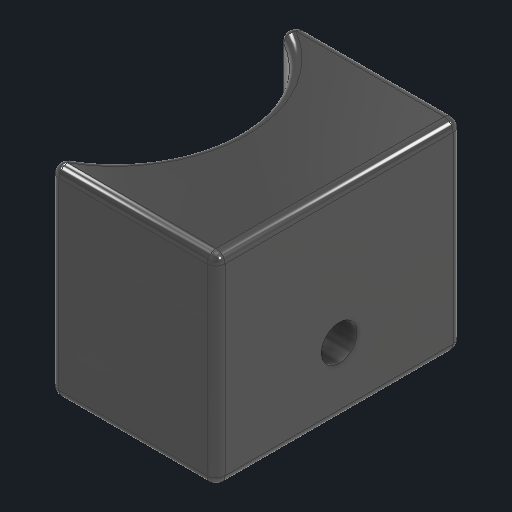
# Autodesk Inventor part: CylinderEndEffector
Saved by Autodesk Inventor 2027.1 (Build 311270010, 270A)
## iProperties
Created: 2026-10-14
Part Number: CylinderEndEffector
Material: PC/ABS Plastic
Document SubType Name: Modeling
Designer: SDS Scholar
Density: 1.1 g/cm^3
Appearance: Smooth - White
Mass: 74.7536 g
Surface Area: 116.939 cm^2
Volume: 67.9578 cm^3
Author: SDS Scholar
Autodesk Inventor part; units mm, degrees
ref_plane "YZ Plane" through (0, 0, 0) normal (1, 0, 0) x (0, 1, 0)
ref_plane "XZ Plane" through (0, 0, 0) normal (0, 1, 0) x (-1, 0, 0)
ref_plane "XY Plane" through (0, 0, 0) normal (0, 0, 1) x (1, 0, 0)
sketch "Sketch1" plane through (0, 0, 0) normal (0, 1, 0) x (-1, 0, 0)
  circle A0 centre (0, 0) radius 27.5
  line L0 (0, 27.5) -> (-50, 27.5)
  line L1 (27.5, 0) -> (-27.5, 0) construction
  line L2 (0, -27.5) -> (-50, -27.5)
  line L3 (-50, -27.5) -> (-50, 27.5)
  point P0 (0, -27.5)
  dimension "d0" = 55
  dimension "d1" = 50
  constraints: 8 end point, 3 point on circle, 2 coincident, 2 horizontal, 2 symmetric about line, 1 centre point, 1 midpoint, 1 tangent, 1 vertical
  measures "d0" diameter of A0
  measures "d1" distance of L0.start L0.end
extrude "Extrusion1" add sketch "Sketch1" along normal blind 45 contours A0 L2 L3 L0
sketch "Sketch2" plane through (50, 0, 27.5) normal (1, 0, 0) x (0, 0, -1)
  circle A0 centre (27.5, 15) radius 2.7
  line L0 (0, 0) -> (55, 0) projected
  line L1 (55, 0) -> (55, 45) projected
  line L2 (0, 45) -> (55, 45) projected
  line L3 (0, 0) -> (0, 45) projected
  line L4 (27.5, 45) -> (27.5, 0) construction
  point P0 (27.5, 0)
  dimension "d5" = 5.4
  dimension "d6" = 15
  constraints: 2 end point, 2 midpoint, 1 centre point, 1 perpendicular, 1 point on line
  measures "d5" diameter of A0
  measures "d6" distance from line of L0 A0.centre
hole "Hole1" at (50, 15, 0) direction (-1, 0, 0) diameter 6 depth 15 counterbore diameter 8 counterbore depth 10
fillet "Fillet1" radius 2 10 edges at (0, 22.5, -27.5) (0, 22.5, 27.5) (25, 45, 27.5) (50, 22.5, 27.5) (50, 45, 0) (25, 0, 27.5) (25, 0, -27.5) (50, 0, 0) (50, 22.5, -27.5) (25, 45, -27.5)
fillet "Fillet2" radius 2 10 edges at (13.0987, 45, 24.5028) (27.5, 45, 0) (13.0987, 45, -24.5028) (13.4182, 44.4142, -26.9142) (13.4182, 44.4142, 26.9142) (13.0987, 0, 24.5028) (13.4182, 0.5858, 26.9142) (13.0987, 0, -24.5028) (13.4182, 0.5858, -26.9142) (27.5, 0, 0)
equation "\"d3\" = ProductTotalHeight"
equation "\"GridProcutClearance\" = 5"
equation "\"GridBorderThickness\" = 5"
equation "\"GridBorderFillets\" = 7"
equation "\"GridTotalSize\" = 65"
equation "\"GridRobotClearance\" = 65"
equation "\"AluminiumExtrusionClearance\" = 35"
equation "\"BaseTotalLength\" = 885"
equation "\"WorkspaceLength\" = 515"
equation "\"WorkspaceHeight\" = 183"
equation "\"AxesBaseFillet\" = 15"
equation "\"Zaxis\" = 197"
equation "\"ProductTotalHeight\" = 45"
equation "\"VerticalStroke\" = 105"
equation "\"BackArea\" = 165"
equation "\"CylinderStroke\" = 75"
equation "\"BoxesWidth\" = 125"
equation "\"BaseWoodThickness\" = 7"
equation "\"kerf\" = 1.5"
equation "\"Kerf\" = 0.3"
equation "\"RxThickness\" = 1.8"
equation "\"support_2\" = 265"
body "Solid1"
